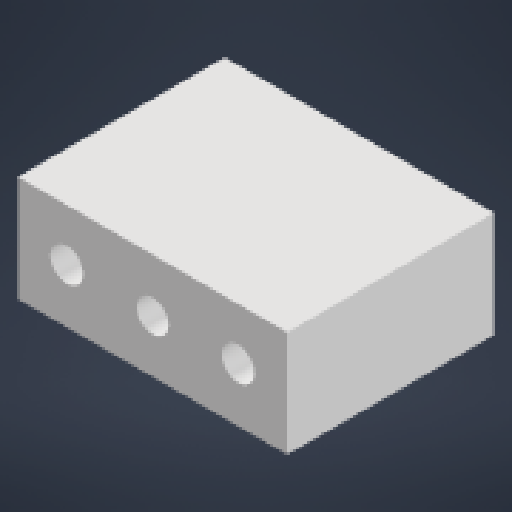
# Autodesk Inventor part: BaseRodilloY
Saved by Autodesk Inventor 2027.1 (Build 311270010, 270A)
## iProperties
Created: 2026-11-02
Part Number: BaseRodilloY
Material: Genérico
Document SubType Name: Modeling
Designer: MANGEL
Density: 1 g/cm^3
Appearance: Valor por defecto
Author: MANGEL
Autodesk Inventor part; units mm, degrees
ref_plane "YZ Plane" through (0, 0, 0) normal (1, 0, 0) x (0, 1, 0)
ref_plane "XZ Plane" through (0, 0, 0) normal (0, 1, 0) x (-1, 0, 0)
ref_plane "XY Plane" through (0, 0, 0) normal (0, 0, 1) x (1, 0, 0)
sketch "Boceto1" plane through (0, 0, 0) normal (0, 0, 1) x (1, 0, 0)
  line L0 (-65.3, -25.65) -> (65.3, -25.65)
  line L1 (65.3, -25.65) -> (65.3, 25.65)
  line L2 (65.3, 25.65) -> (-65.3, 25.65)
  line L3 (-65.3, 25.65) -> (-65.3, -25.65)
  line L4 (-65.3, -25.65) -> (65.3, 25.65) construction
  line L5 (65.3, -25.65) -> (-65.3, 25.65) construction
  point P0 (0, 0)
  dimension "d0" = 130.6
  dimension "d2" = 51.3
  constraints: 12 end point, 2 midpoint, 2 parallel, 1 horizontal, 1 perpendicular
  measures "d0" distance of L1.end L2.end
  measures "d2" distance of L2.end L0.start
extrude "Extrusión1" add sketch "Boceto1" along normal blind 100.3
sketch "Boceto2" plane through (0, 0, 100.3) normal (0, 0, 1) x (1, 0, 0)
  circle A0 centre (0, 0) radius 7.75
  circle A1 centre (41.5, 0.65) radius 8
  line L0 (65.3, 25.65) -> (-65.3, 25.65) construction
  line L1 (0, 25.65) -> (0, 0) construction
  line L2 (65.3, -25.65) -> (65.3, 25.65) construction
  circle A2 centre (-41.5, 0.65) radius 8
  dimension "d5" = 15.5
  dimension "d6" = 16
  dimension "d8" = 25
  dimension "d11" = 41.5
  constraints: 3 centre point, 2 end point, 1 coincident, 1 midpoint, 1 symmetric about line, 1 vertical, 1 other
  measures "d5" diameter of A0
  measures "d6" diameter of A1
  measures "d8" distance from line of L0 A1.centre
  measures "d11" horizontal distance of A1.centre point (0, 0)
extrude "Extrusión2" cut sketch "Boceto2" against normal blind 130
